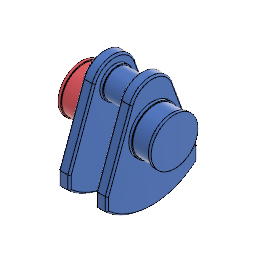
Crank v0 (Autodesk Fusion 360 design; units mm, degrees)
Autodesk Fusion 360 part; units mm, degrees
sketch "Sketch1" plane through (0, 0, 0) normal (1, 0, 0) x (0, 1, 0)
  circle A0 centre (0, 0) radius 40
  line L0 (-37.5877, 13.6808) -> (-81.1936, -106.1253)
  line L1 (-28.0083, 40) -> (134.1892, 40) construction
  line L2 (0, -130) -> (-81.1936, -130)
  line L3 (-81.1936, -106.1253) -> (-81.1936, -130)
  line L4 (37.5877, 13.6808) -> (81.1936, -106.1253)
  line L5 (81.1936, -106.1253) -> (81.1936, -130)
  line L6 (0, -130) -> (81.1936, -130)
  arc A1 (-81.1936, -130) -> (81.1936, -130) centre (0, -40) ccw
  point P0 (0, 20)
  dimension "d1" = 80
  dimension "d2" = 110
  dimension "d3" = 20
  constraint coincident A0.centre origin
  constraint horizontal L1
  constraint tangent A0 L0
  constraint coincident A0 L0.start
  constraint horizontal L2
  constraint perpendicular L2 L3
  constraint coincident A0 A1.centre
  measures "d1" diameter of A0
  measures "d2" angle of L0 L1
  measures "d3" distance of A0.centre P0
sketch "Sketch2" plane through (0, 0, 0) normal (0, 1, 0) x (1, 0, 0)
  line L0 (-43.5, 0) -> (-83.5, 0)
  line L1 (-83.5, -2) -> (-83.5, 40)
  line L2 (-83.5, 40) -> (-43.5, 40)
  line L3 (-43.5, 40) -> (-43.5, -2)
  line L4 (-78.5, 0) -> (-78.5, -2)
  line L5 (-48.5, 0) -> (-48.5, -2)
  line L6 (-83.5, -2) -> (-78.5, -2)
  line L7 (-48.5, -2) -> (-43.5, -2)
  line L8 (0, -13.6808) -> (0, 106.1253)
  line L9 (48.5, -2) -> (43.5, -2)
  line L10 (83.5, -2) -> (78.5, -2)
  line L11 (83.5, 40) -> (43.5, 40)
  line L12 (83.5, -2) -> (83.5, 40)
  line L13 (78.5, 0) -> (78.5, -2)
  line L14 (43.5, 0) -> (83.5, 0)
  line L15 (48.5, 0) -> (48.5, -2)
  line L16 (43.5, 40) -> (43.5, -2)
  line L17 (-83.5, 40) -> (-63.5, 40)
  line L18 (-63.5, 40) -> (-63.5, 25)
  line L19 (-63.5, 25) -> (-83.5, 25)
  line L20 (-83.5, 25) -> (-83.5, 40)
  dimension "d5" = 43.5
  dimension "d6" = 40
  dimension "d7" = 40
  dimension "d9" = 2
  dimension "d10" = 5
  dimension "d11" = 20
  dimension "d12" = 15
  constraint horizontal L0
  constraint vertical L1
  constraint horizontal L2
  constraint vertical L3
  constraint horizontal L6
  constraint coincident L0.end L1
  constraint coincident L3.end L6
  constraint coincident L0.start L3
  constraint perpendicular L4 L6
  constraint perpendicular L0 L5
  constraint collinear L6 L7
  constraint coincident L0 L4.start
  constraint coincident L0 L5.start
  constraint equal L6 L7
  constraint symmetric L0.start L8 L14.start
  constraint symmetric L0.end L8 L14.end
  constraint symmetric L1.end L8 L11.start
  constraint symmetric L2.end L8 L11.end
  constraint symmetric L1.start L8 L10.start
  constraint symmetric L3.end L8 L9.end
  constraint symmetric L4.end L8 L10.end
  constraint symmetric L5.end L8 L9.start
  constraint symmetric L4.start L8 L13.start
  constraint symmetric L5.start L8 L15.start
  constraint horizontal L17
  constraint vertical L18
  constraint horizontal L19
  constraint vertical L20
  measures "d5" distance of origin L0.start
  measures "d6" distance of L0.start L0.end
  measures "d7" distance of L0.end L1.end
  measures "d9" distance of L4.end L4.start
  measures "d10" distance of L1.start L4.end
  measures "d11" distance of L1.end L17.end
  measures "d12" distance of L1.end L19.end
extrude "Extrude1" add sketch "Sketch1" against normal blind 20 from surface at 43.5 makes body 1
mirror "Mirror1" about plane through (0, 0, 0) normal (1, 0, 0) of "Extrude1" makes body 2
revolve "Revolve1" add sketch "Sketch2" angle 360 about axis through (83.5, 0, -40) along (-1, 0, 0) separate body contours L0 L3 L5 L7 | L0 L1 L2 L3 L18 L19 | L0 L1 L4 L6 | L9 L14 L15 L16 | L11 L12 L14 L16 | L10 L12 L13 L14 makes body 3 at (-58.5, -1.9938, -0.0497) makes body 4 at (58.5, -1.9938, -0.0497)
sketch "Sketch3" plane through (0, 0, 0) normal (0, 1, 0) x (1, 0, 0)
  line L0 (-43.5, -13.6808) -> (-43.5, 106.1253)
  line L1 (-43.5, 106.1253) -> (-23.5, 106.1253)
  line L2 (-23.5, 106.1253) -> (-23.5, -13.6808)
  line L3 (-23.5, -13.6808) -> (-43.5, -13.6808)
  line L4 (43.5, 106.1253) -> (43.5, -13.6808)
  line L5 (43.5, -13.6808) -> (23.5, -13.6808)
  line L6 (23.5, -13.6808) -> (23.5, 106.1253)
  line L7 (23.5, 106.1253) -> (43.5, 106.1253)
  line L8 (-23.5, 0) -> (23.5056, 0)
  line L9 (23.5056, 0) -> (23.5056, -27)
  line L10 (23.5056, -25) -> (-23.5, -25)
  line L11 (-23.5, -27) -> (-23.5, 0)
  line L12 (-18.5, -25) -> (-18.5, -27)
  line L13 (18.5056, -25) -> (18.5056, -27)
  line L14 (-23.5, -27) -> (-18.5, -27)
  line L15 (18.5056, -27) -> (23.5056, -27)
  dimension "d19" = 25
  dimension "d21" = 5
  dimension "d22" = 5
  constraint horizontal L8
  constraint vertical L9
  constraint horizontal L10
  constraint vertical L11
  constraint coincident L2 L8.start
  constraint horizontal L14
  constraint coincident L9.end L14
  constraint coincident L10.start L9
  constraint coincident L10.end L11
  constraint perpendicular L10 L12
  constraint perpendicular L10 L13
  constraint collinear L14 L15
  constraint coincident L10 L12.start
  constraint coincident L10 L13.start
  measures "d19" distance of L8.start L10.end
  measures "d21" distance of L9.end L13.end
  measures "d22" distance of L11.start L12.end
revolve "Revolve2" add sketch "Sketch3" angle 360 about axis through (-23.5, 0, 0) along (1, 0, 0) separate body contours L2 L5 L6 L8 L9 L10 L11 | L10 L11 L12 L14 | L9 L10 L13 L15 makes body 5
fillet "Fillet1" radius 3 24 edges at (23.5, -59.3906, -46.2223) (23.5, 0, 40) (23.5, 59.3906, -46.2223) (43.5, 59.3906, -46.2223) (43.5, 0, 40) (43.5, -59.3906, -46.2223) (23.5, 81.1936, -118.0627) (43.5, 81.1936, -118.0627) (23.5, 0, -161.2122) (43.5, 0, -161.2122) (23.5, -81.1936, -118.0627) (43.5, -81.1936, -118.0627) (-43.5, 59.3906, -46.2223) (-43.5, 0, 40) (-43.5, -59.3906, -46.2223) (-23.5, -59.3906, -46.2223) (-23.5, 0, 40) (-23.5, 59.3906, -46.2223) (-43.5, 81.1936, -118.0627) (-23.5, 81.1936, -118.0627) (-43.5, 0, -161.2122) (-23.5, 0, -161.2122) (-43.5, -81.1936, -118.0627) (-23.5, -81.1936, -118.0627) on bodies 1 2
combine "Combine1" operation add target body 1 tool bodies 2 5
copy_body "Body->Comp1" bodies 1 removing the originals makes body 6 in component "CRANK"
copy_body "CutPasteBodies1" bodies 4 removing the originals makes body 7 in component "CRANK"
copy_body "Body->Comp2" bodies 3 removing the originals makes body 8 in component "ROTOR"
component "CRANK" placed x (1, 0, 0) y (0, 1, 0) z (0, 0, 1) at (0, 0, 0)
component "ROTOR" placed x (1, 0, 0) y (0, 1, 0) z (0, 0, 1) at (0, 0, 0)
